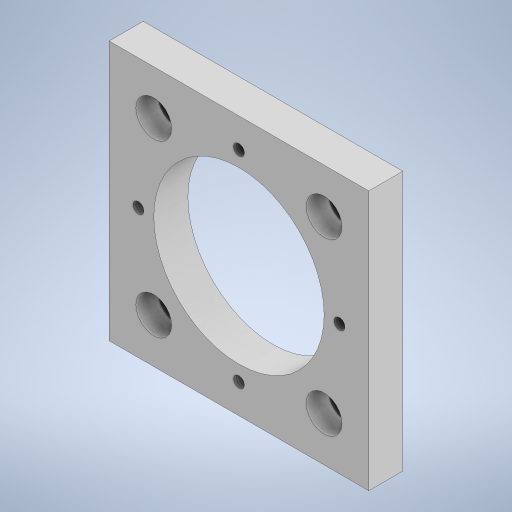
# Autodesk Inventor part: PRS-110-Adapterbase_V2
Saved by Autodesk Inventor 2023 (Build 270158000, 158)
## iProperties
Created: 2023-07-07
Part Number: PRS-110-Adapterbase_V2
Material: Generic
Document SubType Name: Modeling
Designer: B0067-WS-2
Density: 1 g/cm^3
Appearance: Default
Author: B0067-WS-2
Autodesk Inventor part; units mm, degrees
ref_plane "YZ Plane" through (0, 0, 0) normal (1, 0, 0) x (0, 1, 0)
ref_plane "XZ Plane" through (0, 0, 0) normal (0, 1, 0) x (-1, 0, 0)
ref_plane "XY Plane" through (0, 0, 0) normal (0, 0, 1) x (1, 0, 0)
sketch "Sketch1" plane through (0, 0, 0) normal (0, 0, 1) x (1, 0, 0)
  line L0 (-53.34, 0) -> (53.34, 0) construction
  line L1 (0, -53.34) -> (0, 53.34) construction
  line L2 (-38.1, 38.1) -> (38.1, 38.1)
  line L3 (38.1, 38.1) -> (38.1, -38.1)
  line L4 (38.1, -38.1) -> (-38.1, -38.1)
  line L5 (-38.1, -38.1) -> (-38.1, 38.1)
  circle A0 centre (0, 0) radius 25
  dimension "d0" = 76.2
  dimension "d1" = 76.2
  dimension "d13" = 50
  constraints: 8 end point, 2 parallel, 1 centre point, 1 coincident, 1 horizontal, 1 perpendicular, 2 other
  measures "d0" distance between parallel lines of L4 L2
  measures "d1" distance of L2.start L2.end
  measures "d13" diameter of A0
extrude "Extrusion1" add sketch "Sketch1" along normal blind 10
sketch "Sketch2" plane through (0, 0, 10) normal (0, 0, 1) x (1, 0, 0)
  line L0 (-38.1, -38.1) -> (38.1, -38.1) construction
  line L1 (38.1, -38.1) -> (38.1, 38.1) construction
  line L2 (38.1, 38.1) -> (-38.1, 38.1) construction
  line L3 (-38.1, 38.1) -> (-38.1, -38.1) construction
  line L4 (-25, 25) -> (25, 25) construction
  line L5 (25, 25) -> (25, -25) construction
  line L6 (25, -25) -> (-25, -25) construction
  line L7 (-25, -25) -> (-25, 25) construction
  line L8 (-53.34, 0) -> (53.34, 0) construction
  line L9 (0, -53.34) -> (0, 53.34) construction
  point P0 (0, 0)
  dimension "d4" = 50
  dimension "d5" = 50
  constraints: 8 end point, 4 coincident, 2 parallel, 1 horizontal, 1 perpendicular, 2 other
  measures "d4" distance between parallel lines of L6 L4
  measures "d5" distance of L4.start L4.end
hole "Hole1" at (-25, 25, 10) at (25, 25, 10) at (25, -25, 10) at (-25, -25, 10) direction (0, 0, -1) diameter 6 end through all counterbore diameter 10.5 counterbore depth 6.5
sketch "Sketch3" plane through (0, 0, 10) normal (0, 0, 1) x (1, 0, 0)
  circle A0 centre (25, -25) radius 5.25 construction
  circle A1 centre (-25, 25) radius 5.25 construction
  circle A2 centre (25, 25) radius 5.25 construction
  circle A3 centre (-25, -25) radius 5.25 construction
  line L0 (-38.1, -38.1) -> (38.1, -38.1) construction
  line L1 (38.1, -38.1) -> (38.1, 38.1) construction
  line L2 (38.1, 38.1) -> (-38.1, 38.1) construction
  line L3 (-38.1, 38.1) -> (-38.1, -38.1) construction
  circle A4 centre (0, 0) radius 25 construction
  circle A5 centre (0, 0) radius 29.5 construction
  point P0 (0, 29.5)
  point P1 (-29.5, 0)
  point P2 (29.5, 0)
  point P3 (0, -29.5)
  dimension "d14" = 59
  constraints: 4 point on circle, 1 centre point, 1 coincident
  measures "d14" diameter of A5
hole "Hole2" at (0, 29.5, 10) at (-29.5, 0, 10) at (29.5, 0, 10) at (0, -29.5, 10) direction (0, 0, -1) diameter 3.242 end through all thread size "M4x0.7" class "6H" standard "ANSI Metric M Profile"
body "Solid1"
